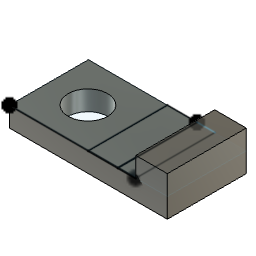
rpi_stand_top_fastener (Autodesk Fusion 360 design; units mm, degrees)
Autodesk Fusion 360 part; units mm, degrees
sketch "Sketch1" plane through (0, 0, 0) normal (0, 0, 1) x (1, 0, 0)
  line L0 (0, 0) -> (16, 0)
  line L1 (16, 0) -> (16, 8)
  line L2 (16, 8) -> (0, 8)
  line L3 (0, 8) -> (0, 0)
  dimension "d1" = 16
  dimension "d2" = 8
  constraint horizontal L0
  constraint vertical L1
  constraint horizontal L2
  constraint vertical L3
  constraint coincident L0.start L3.end
  measures "d1" distance of L0.start L0.end
  measures "d2" distance of L0.start L2.end
extrude "Extrude1" add sketch "Sketch1" along normal blind 2
sketch "Sketch2" plane through (0, 0, 2) normal (0, 0, 1) x (-1, 0, 0)
  line L0 (0, -8) -> (0, 0)
  line L1 (0, 0) -> (-16, 0)
  line L2 (-16, 0) -> (-16, -8)
  line L3 (-16, -8) -> (0, -8)
  line L4 (0, 0) -> (-8, 0)
  line L5 (-8, 0) -> (-11, 0)
  line L6 (-11, 0) -> (-12.8, 0)
  line L7 (-11, 0) -> (-12.8, 0)
  line L8 (-12.8, 0) -> (-12.8, -8.0236)
  line L9 (-12.8, -8.0236) -> (-11, -8.0236)
  line L10 (-11, -8.0236) -> (-11, 0)
  line L11 (-8, 0) -> (-11, 0)
  line L12 (-11, 0) -> (-11, -8)
  line L13 (-11, -8) -> (-8, -8)
  line L14 (-8, -8) -> (-8, 0)
  dimension "d5" = 8
  dimension "d6" = 3
  dimension "d7" = 1.8
  dimension "d8" = 1.8
  dimension "d11" = 8
  dimension "d12" = 3
  dimension "d13" = 1.8
  constraint coincident L0.end L1.start
  constraint perpendicular L0 L4
  constraint parallel L1 L5
  constraint parallel L1 L6
  constraint horizontal L7
  constraint vertical L8
  constraint horizontal L9
  constraint vertical L10
  constraint horizontal L11
  constraint vertical L12
  constraint horizontal L13
  constraint vertical L14
  constraint coincident L3 L12.end
  constraint coincident L10 L12.end
  measures "d5" distance of L0.end L4.end
  measures "d6" distance of L4.end L5.end
  measures "d7" distance of L5.end L6.end
  measures "d8" distance of L5.end L6.end
  measures "d11" distance of L0.end L4.end
  measures "d12" distance of L4.end L5.end
  measures "d13" distance of L5.end L6.end
extrude "Extrude3" add sketch "Sketch2" along normal blind 2 contours L1 L2 L3 L8
sketch "Sketch3" plane through (0, 0, 2) normal (0, 0, 1) x (-1, 0, 0)
  circle A0 centre (-3.9486, -4) radius 2
  dimension "d16" = 4
  measures "d16" diameter of A0
extrude "Extrude4" cut sketch "Sketch3" against normal blind 2
